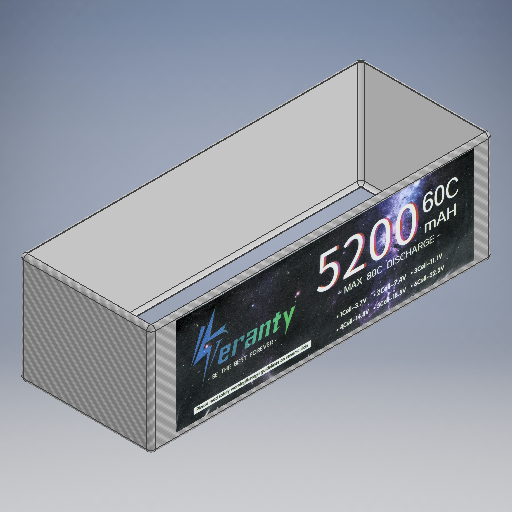
# Autodesk Inventor part: Wrapper
Saved by Autodesk Inventor 2025 (Build 290162010, 162A)
## iProperties
Created: 2025-08-20
Part Number: Wrapper
Material: Generic
Document SubType Name: Modeling
Designer: Glen Collingwood
Density: 1 g/cm^3
Appearance: Default
Author: Glen Collingwood
Autodesk Inventor part; units mm, degrees
ref_plane "YZ Plane" through (0, 0, 0) normal (1, 0, 0) x (0, 1, 0)
ref_plane "XZ Plane" through (0, 0, 0) normal (0, 1, 0) x (-1, 0, 0)
ref_plane "XY Plane" through (0, 0, 0) normal (0, 0, 1) x (1, 0, 0)
sketch "Sketch1" plane through (0, 0, 0) normal (0, 0, 1) x (1, 0, 0)
  line L0 (24, 133) -> (-24, 133)
  line L1 (-25.5, 131.5) -> (-25.5, 1.5)
  line L2 (-24, 0) -> (24, 0)
  line L3 (25.5, 1.5) -> (25.5, 131.5)
  line L4 (25.5, 1.5) -> (25.5, 118.5) projected
  line L5 (-25.5, 118.5) -> (-25.5, 1.5) projected
  arc A0 (-25.5, 1.5) -> (-24.7808, 0.2192) centre (-24, 1.5) ccw projected
  line L6 (-12.0179, 0) -> (-14.5, 0) projected
  arc A1 (24.7808, 0.2192) -> (25.5, 1.5) centre (24, 1.5) ccw projected
  arc A2 (-25.5, 1.5) -> (-24, 0) centre (-24, 1.5) ccw
  arc A3 (24, 0) -> (25.5, 1.5) centre (24, 1.5) ccw
  arc A4 (-24, 133) -> (-25.5, 131.5) centre (-24, 131.5) ccw
  arc A5 (25.5, 131.5) -> (24, 133) centre (24, 131.5) ccw
  line L7 (-24, 133.25) -> (24, 133.25)
  arc A6 (25.75, 131.5) -> (24, 133.25) centre (24, 131.5) ccw
  line L8 (25.75, 131.5) -> (25.75, 1.5)
  arc A7 (24, -0.25) -> (25.75, 1.5) centre (24, 1.5) ccw
  line L9 (24, -0.25) -> (-24, -0.25)
  arc A8 (-25.75, 1.5) -> (-24, -0.25) centre (-24, 1.5) ccw
  line L10 (-25.75, 1.5) -> (-25.75, 131.5)
  arc A9 (-24, 133.25) -> (-25.75, 131.5) centre (-24, 131.5) ccw
  point P0 (0, 0)
  point P1 (-25.5, 1.5)
  point P2 (-24.7808, 0.2192)
  point P3 (24.7808, 0.2192)
  dimension "d0" = 1.5
  dimension "d1" = 133
  dimension "d2" = 1.5
  dimension "d3" = 0.25
  constraints: 16 end point, 16 point on circle, 8 centre point, 8 tangent, 4 parallel, 3 collinear, 2 equal radius, 2 perpendicular, 1 horizontal, 7 other
  measures "d0" radius of A2
  measures "d1" distance between parallel lines of L2 L0
  measures "d2" radius of A4
  measures "d3" distance between parallel lines of L0 L7
extrude "Extrusion1" add sketch "Sketch1" along normal mid plane 40
sketch "Sketch2" plane through (0, 0, 0) normal (1, 0, 0) x (0, 1, 0)
  line L0 (133.25, -20) -> (133, -20) projected
  line L1 (133, 20) -> (133.25, 20) projected
  line L2 (133.25, 20) -> (133.25, -20) projected
  line L3 (-0.25, -20) -> (-0.25, 20) projected
  line L4 (131.5, 20) -> (1.5, 20) projected
  circle A0 centre (131.75, 20) radius 1.5
  circle A1 centre (131.75, 20) radius 1.25
  line L5 (131.75, 20) -> (131.75, 21.5)
  line L6 (133, -20) -> (133, 20) projected
  line L7 (0, -20) -> (-0.25, -20) projected
  line L8 (-0.25, 20) -> (0, 20) projected
  line L9 (0, 20) -> (0, -20) projected
  point P0 (0, 0)
  point P1 (131.75, 21.25)
  point P2 (130.25, 19.5)
  point P3 (133, 19.5)
  point P4 (131.75, 19.5)
  point P5 (133, 19.1708)
  dimension "d6" = 3
  constraints: 2 centre point, 2 end point, 2 point on circle, 1 coincident, 1 point on line, 1 tangent
  measures "d6" diameter of A0
sketch3d "3D Sketch1"
  line L0 (24, -0.25, 20) -> (-24, -0.25, 20)
  arc A0 (-24, -0.25, 20) -> (-25.75, 1.5, 20) centre (-24, 1.5, 20) ccw
  line L1 (-25.75, 1.5, 20) -> (-25.75, 131.5, 20)
  arc A1 (-25.75, 131.5, 20) -> (-24, 133.25, 20) centre (-24, 131.5, 20) ccw
  line L2 (-24, 133.25, 20) -> (24, 133.25, 20)
  arc A2 (24, 133.25, 20) -> (25.75, 131.5, 20) centre (24, 131.5, 20) ccw
  line L3 (25.75, 131.5, 20) -> (25.75, 1.5, 20)
  arc A3 (25.75, 1.5, 20) -> (24, -0.25, 20) centre (24, 1.5, 20) ccw
sweep "Sweep1" add profiles "Sketch2" path "3D Sketch1" contours L0 L6 A0 L2 | L1 A1 L5 A0
mirror "Mirror1" about plane through (0, 0, 0) normal (0, 0, 1) of "Sweep1"
ref_plane "Work Plane1" through (-30.75, 1.5, 20) normal (-1, 0, 0) x (0, 0, 1)
sketch "Sketch4" plane through (-30.75, 1.5, 20) normal (-1, 0, 0) x (0, 0, 1)
  line L0 (-0.3147, 5.6055) -> (-38.3971, 5.6055) construction
  line L1 (-38.3971, 5.6055) -> (-38.3971, 122.162) construction
  line L2 (-38.3971, 122.162) -> (-0.3147, 122.162) construction
  line L3 (-0.3147, 122.162) -> (-0.3147, 5.6055) construction
  point P0 (-20, -1.5)
  constraints: 2 other
decal "Decal2"
ref_plane "Work Plane2" through (30.75, 1.5, 20) normal (1, 0, 0) x (0, 0, -1)
sketch "Sketch5" plane through (30.75, 1.5, 20) normal (1, 0, 0) x (0, 0, -1)
  line L0 (2.1201, 27.0435) -> (2.1201, 106.5878) construction
  line L1 (2.1201, 106.5878) -> (36.7911, 106.5878) construction
  line L2 (36.7911, 106.5878) -> (36.7911, 27.0435) construction
  line L3 (36.7911, 27.0435) -> (2.1201, 27.0435) construction
  point P0 (20, -1.5)
  constraints: 2 other
decal "Decal3"
body "Solid1"
